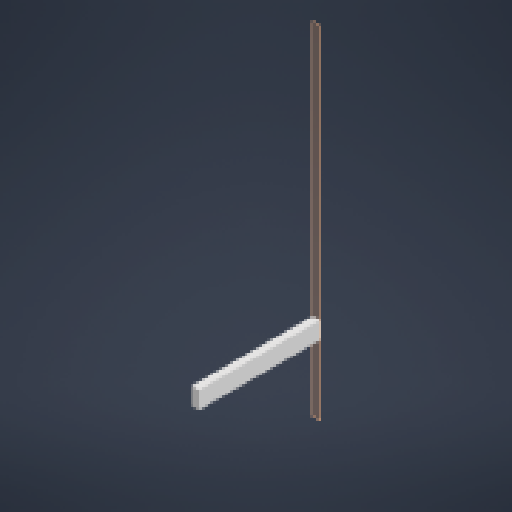
# Autodesk Inventor part: 2x4x26.2
Saved by Autodesk Inventor 2027 (Build 310192000, 192)
## iProperties
Created: 2026-10-18
Part Number: 2x4x26.2
Material: Generic
Document SubType Name: Modeling
Designer: lucas
Density: 1 g/cm^3
Appearance: Default
Author: lucas
Autodesk Inventor part; units mm, degrees
ref_plane "YZ Plane" through (0, 0, 0) normal (1, 0, 0) x (0, 1, 0)
ref_plane "XZ Plane" through (0, 0, 0) normal (0, 1, 0) x (-1, 0, 0)
ref_plane "XY Plane" through (0, 0, 0) normal (0, 0, 1) x (1, 0, 0)
ref_plane "Work Plane1" through (0, 0, 0) normal (0, 0, 1) x (1, 0, 0)
sketch "Sketch1" plane through (0, 0, 0) normal (0, 0, 1) x (1, 0, 0)
  line L0 (0, 0) -> (38.1, 0) projected
  line L1 (38.1, 0) -> (38.1, 1600.2) projected
  line L2 (0, 1600.2) -> (38.1, 1600.2) projected
  line L3 (0, 0) -> (0, 1600.2) projected
  line L4 (0, 279.4) -> (38.1, 279.4)
  line L5 (38.1, 279.4) -> (38.1, 368.3)
  line L6 (38.1, 368.3) -> (0, 368.3)
  line L7 (0, 368.3) -> (0, 279.4)
  point P0 (19.05, 368.3)
  point P1 (0, 368.3)
  point P2 (38.1, 279.4)
  dimension "d0" = 88.9
  constraints: 8 end point, 2 parallel, 2 point on line, 1 horizontal, 1 midpoint, 1 perpendicular
  measures "d0" distance from line of L4 point (19.05, 368.3)
extrude "Extrusion1" add sketch "Sketch1" along normal blind 622.3 contours L3 L6 L1 L4
body "Solid1"
